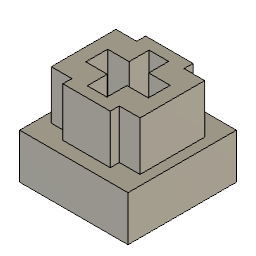
adapter_mitsumi_regular_keycap_to_medium_low_cherry_switch (Autodesk Fusion 360 design; units mm, degrees)
part number: 2025-08-08-07-57-11-053
Autodesk Fusion 360 part; units mm, degrees
sketch "Cherry outer profile" plane through (0, 0, 0) normal (0, 0, 1) x (1, 0, 0)
  line L0 (-2.95, 2.15) -> (2.95, 2.15)
  line L1 (2.95, 2.15) -> (2.95, -2.15)
  line L2 (2.95, -2.15) -> (-2.95, -2.15)
  line L3 (-2.95, -2.15) -> (-2.95, 2.15)
  line L4 (-2.95, 2.15) -> (2.95, -2.15) construction
  line L5 (2.95, 2.15) -> (-2.95, -2.15) construction
  line L6 (-1.575, 2.15) -> (1.575, 2.15)
  line L7 (1.575, 2.15) -> (1.575, 2.75)
  line L8 (1.575, 2.75) -> (-1.575, 2.75)
  line L9 (-1.575, 2.75) -> (-1.575, 2.15)
  line L10 (-1.575, -2.15) -> (1.575, -2.15)
  line L11 (1.575, -2.15) -> (1.575, -2.75)
  line L12 (1.575, -2.75) -> (-1.575, -2.75)
  line L13 (-1.575, -2.75) -> (-1.575, -2.15)
  dimension "d4" = 5.9
  dimension "d5" = 4.3
  dimension "d10" = 0.6
  dimension "d15" = 3.15
  dimension "d17" = 1.375
  dimension "d18" = 1.375
  dimension "d19" = 3.15
  dimension "d20" = 1.375
  dimension "d21" = 1.375
  dimension "d22" = 0.6
  constraint horizontal L0
  constraint perpendicular L0 L1
  constraint parallel L0 L2
  constraint parallel L1 L3
  constraint coincident L4 origin
  constraint coincident L5 origin
  constraint horizontal L6
  constraint vertical L7
  constraint horizontal L8
  constraint vertical L9
  constraint coincident L0 L6.start
  constraint horizontal L10
  constraint vertical L11
  constraint horizontal L12
  constraint vertical L13
  constraint coincident L2 L10.start
  measures "d4" distance of L0.start L0.end
  measures "d5" distance of L0.start L2.end
  measures "d10" distance of L6.start L8.end
  measures "d15" distance of L7.end L8.end
  measures "d17" distance of L0.start L6.start
  measures "d18" distance of L0.end L6.end
  measures "d19" distance of L11 L13
  measures "d20" distance of L3 L13
  measures "d21" distance of L1.end L11
  measures "d22" distance of L2 L12.end
sketch "Cherry inner profile" plane through (0, 0, 0) normal (0, 0, 1) x (1, 0, 0)
  line L0 (0.65, 2.05) -> (-0.65, 2.05)
  line L1 (-0.65, 2.05) -> (-0.65, -2.05)
  line L2 (-0.65, -2.05) -> (0.65, -2.05)
  line L3 (0.65, -2.05) -> (0.65, 2.05)
  line L4 (0.65, 2.05) -> (-0.65, -2.05) construction
  line L5 (-0.65, 2.05) -> (0.65, -2.05) construction
  line L6 (-2.075, 0.725) -> (2.075, 0.725)
  line L7 (2.075, 0.725) -> (2.075, -0.725)
  line L8 (2.075, -0.725) -> (-2.075, -0.725)
  line L9 (-2.075, -0.725) -> (-2.075, 0.725)
  line L10 (-2.075, 0.725) -> (2.075, -0.725) construction
  line L11 (2.075, 0.725) -> (-2.075, -0.725) construction
  dimension "d27" = 1.3
  dimension "d28" = 4.1
  dimension "d31" = 4.15
  dimension "d32" = 1.45
  constraint horizontal L0
  constraint perpendicular L0 L1
  constraint parallel L0 L2
  constraint parallel L1 L3
  constraint coincident L4 origin
  constraint coincident L5 origin
  constraint horizontal L6
  constraint perpendicular L6 L7
  constraint parallel L6 L8
  constraint parallel L7 L9
  constraint coincident L10 origin
  constraint coincident L11 origin
  measures "d27" distance of L0.start L0.end
  measures "d28" distance of L0.start L2.end
  measures "d31" distance of L7.end L8.end
  measures "d32" distance of L6.start L8.end
extrude "Extrude2" add sketch "Cherry outer profile" along normal blind 3.5 makes body 1
extrude "Extrude3" cut sketch "Cherry inner profile" along normal blind 3.85 bodies 1
sketch "Mitsumi profile" plane through (0, 0, 0) normal (0, 0, 1) x (1, 0, 0)
  line L0 (1.55, 1.55) -> (-1.55, 1.55)
  line L1 (-1.55, 1.55) -> (-1.55, -1.55)
  line L2 (-1.55, -1.55) -> (1.55, -1.55)
  line L3 (1.55, -1.55) -> (1.55, 1.55)
  line L4 (1.55, 1.55) -> (-1.55, -1.55) construction
  line L5 (-1.55, 1.55) -> (1.55, -1.55) construction
  line L6 (3.6, 3.6) -> (-3.6, 3.6)
  line L7 (-3.6, 3.6) -> (-3.6, -3.6)
  line L8 (-3.6, -3.6) -> (3.6, -3.6)
  line L9 (3.6, -3.6) -> (3.6, 3.6)
  line L10 (3.6, 3.6) -> (-3.6, -3.6) construction
  line L11 (-3.6, 3.6) -> (3.6, -3.6) construction
  dimension "d38" = 3.1
  dimension "d39" = 3.1
  dimension "d40" = 7.2
  dimension "d41" = 7.2
  constraint horizontal L0
  constraint perpendicular L0 L1
  constraint parallel L0 L2
  constraint parallel L1 L3
  constraint coincident L4 origin
  constraint coincident L5 origin
  constraint horizontal L6
  constraint perpendicular L6 L7
  constraint parallel L6 L8
  constraint parallel L7 L9
  constraint coincident L10 origin
  constraint coincident L11 origin
  measures "d38" distance of L0.start L0.end
  measures "d39" distance of L0.start L2.end
  measures "d40" distance of L6.start L8.end
  measures "d41" distance of L7.end L8.end
extrude "Extrude4" add sketch "Mitsumi profile" against normal blind 4 separate body makes body 2
move_face "MoveFace1" by (0, 0, 0.5) 1 faces at (2.9167, -0.5167, -4) on bodies 2
move_face "MoveFace2" by (0, 0, -0.25) 1 faces at (-1.4333, -1.2, 3.5) on bodies 1
extrude "Extrude5" cut 1 faces at (-0.5167, 2.9167, -3.5) along direction (0, 0, 1) blind 0.5 on bodies 2 bodies 2
equation "d4 = cherry_internal_width - double_tolerance"
equation "d5 = cherry_internal_height - double_tolerance"
equation "cherry_internal_width = 6.1 mm"
equation "cherry_internal_height = 4.5 mm"
equation "tolerance = 0.1 mm"
equation "double_tolerance = tolerance * 2"
equation "cherry_internal_flange_width = 3.35 mm"
equation "d15 = cherry_internal_flange_width - double_tolerance"
equation "d17 = ( cherry_internal_width - cherry_internal_flange_width ) / 2"
equation "d19 = cherry_internal_flange_width - double_tolerance"
equation "d20 = ( cherry_internal_width - cherry_internal_flange_width ) / 2"
equation "cherry_cross_vertical_thickness = 1.1 mm"
equation "cherry_cross_horizontal_thickness = 1.25 mm"
equation "d27 = cherry_cross_vertical_thickness + double_tolerance"
equation "d28 = cherry_cross_height + double_tolerance"
equation "cherry_cross_height = 3.9 mm"
equation "cherry_cross_width = 3.95 mm"
equation "d31 = cherry_cross_width + double_tolerance"
equation "d32 = cherry_cross_horizontal_thickness + double_tolerance"
equation "mitsumi_stem_width = 3 mm"
equation "d38 = mitsumi_stem_width + tolerance"
equation "d39 = mitsumi_stem_width + tolerance"
equation "d40 = mitsumi_stem_width + double_tolerance + 4 mm"
equation "d41 = mitsumi_stem_width + double_tolerance + 4 mm"
equation "half_tolerance = tolerance * 0.5"
